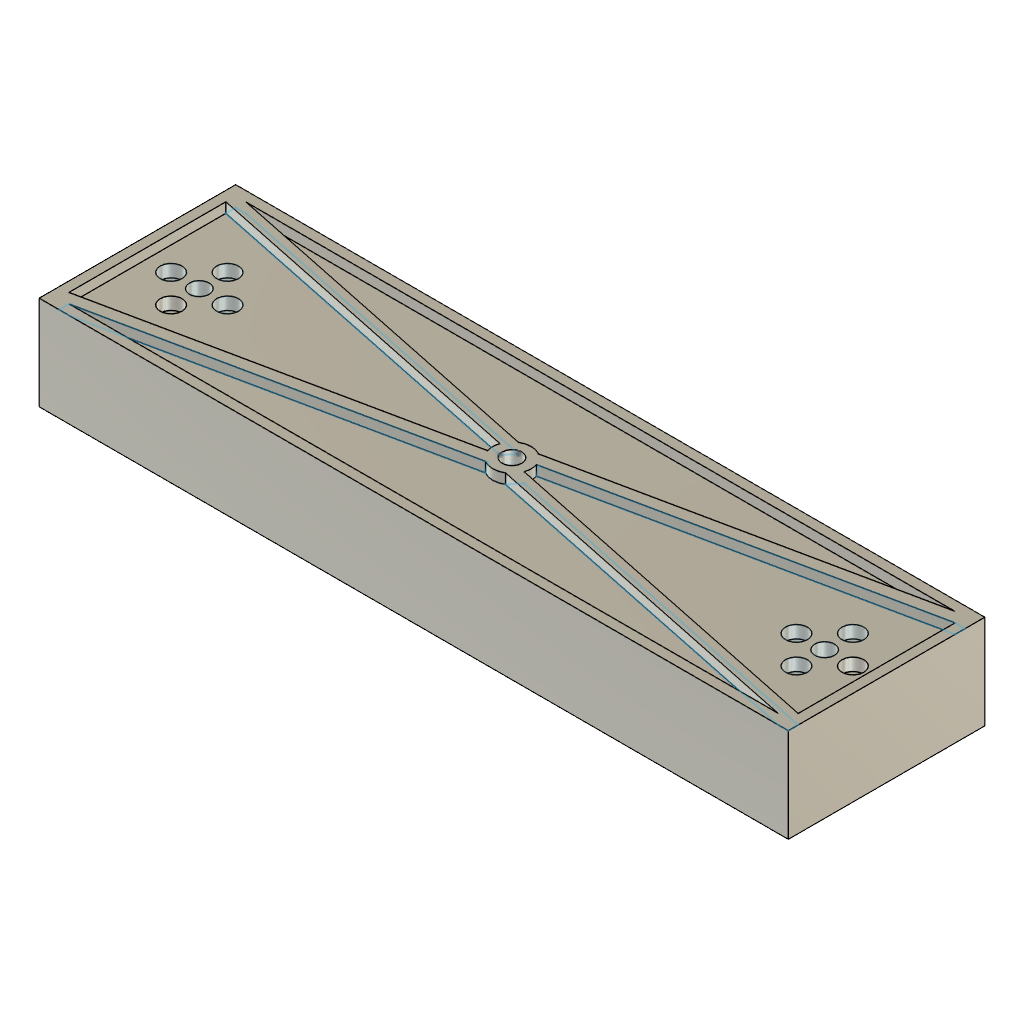
Redesigned_Cossplate (Autodesk Fusion 360 design; units mm, degrees)
part number: 2026-11-11-17-12-47-965
part number: 2026-11-11-17-17-20-266
Autodesk Fusion 360 part; units mm, degrees
sketch "Sketch1" plane through (0, 0, 0) normal (0, 0, 1) x (1, 0, 0)
  line L0 (190.5, 50) -> (-190.5, 50)
  line L1 (-190.5, 50) -> (-190.5, -50)
  line L2 (-190.5, -50) -> (190.5, -50)
  line L3 (190.5, -50) -> (190.5, 50)
  line L4 (190.5, 50) -> (-190.5, -50) construction
  line L5 (-190.5, 50) -> (190.5, -50) construction
  dimension "d1" = 381
  dimension "d2" = 100
  constraint horizontal L0
  constraint perpendicular L0 L1
  constraint parallel L0 L2
  constraint parallel L1 L3
  constraint coincident L4 origin
  constraint coincident L5 origin
  measures "d1" distance of L1.end L2.end
  measures "d2" distance of L0.end L1.end
extrude "Extrude1" add sketch "Sketch1" along normal blind 42.8 makes body 1
sketch "Sketch2" plane through (0, 0, 42.8) normal (0, 0, 1) x (-1, 0, 0)
  line L0 (-190.5, 50) -> (-190.5, -50)
  line L1 (-190.5, -50) -> (190.5, -50)
  line L2 (190.5, -50) -> (190.5, 50)
  line L3 (190.5, 50) -> (-190.5, 50)
  line L4 (190.5, 0) -> (-190.5, 0)
  line L5 (0, -50) -> (0, 50)
  circle A0 centre (159, 0) radius 14.351 construction
  circle A1 centre (159, 0) radius 5
  line L6 (159, -14.351) -> (159, 14.351) construction
  circle A2 centre (-159, 0) radius 14.351 construction
  circle A3 centre (-159, 0) radius 5
  circle A4 centre (0, 0) radius 5
  point P0 (144.649, 0)
  point P1 (173.351, 0)
  point P2 (159, -14.351)
  point P3 (159, 14.351)
  point P4 (-159, -14.351)
  point P5 (-144.649, 0)
  point P6 (-159, 14.351)
  point P7 (-173.351, 0)
  point P8 (-159, -14.351)
  point P9 (-173.351, 0)
  point P10 (-159, 14.351)
  point P11 (-144.649, 0)
  dimension "d5" = 28.702
  dimension "d6" = 10
  dimension "d7" = 31.5
  constraint midpoint L2 L4.start
  constraint midpoint L0 L4.end
  constraint midpoint L1 L5.start
  constraint midpoint L3 L5.end
  constraint coincident L4 A0.centre
  constraint concentric A0 A1
  constraint coincident A0 P0
  constraint coincident L4 P0
  constraint coincident A0 P1
  constraint coincident L4 P1
  constraint coincident A0 P2
  constraint coincident A0 P3
  constraint coincident P2 L6.start
  constraint coincident P3 L6.end
  constraint vertical L6
  constraint coincident A0.centre L6
  constraint symmetric L5 A0 A2
  constraint symmetric L5 A1 A3
  constraint symmetric L5 P0 P5
  constraint symmetric L5 P1 P9
  constraint symmetric L5 P2 P8
  constraint symmetric L5 P3 P10
  constraint coincident A4.centre origin
  constraint equal A1 A4
  constraint coincident P8 P4
  constraint coincident P9 P7
  constraint coincident P10 P6
  constraint coincident P11 P5
  measures "d5" diameter of A0
  measures "d6" diameter of A1
  measures "d7" distance of L2 A0.centre
hole "Hole1" at (-159, 14.351, 42.8) at (-144.649, 0, 42.8) at (-159, -14.351, 42.8) at (-173.351, 0, 42.8) at (144.649, 0, 42.8) at (159, 14.351, 42.8) at (173.351, 0, 42.8) at (159, -14.351, 42.8) direction (0, 0, -1) diameter 6.7564 depth 53.34 tip angle 118 counterbore diameter 11.1252 counterbore depth 6.35 bodies 1
extrude "Extrude2" cut sketch "Sketch2" against normal through all contours L4 A3 | L4 A3 | L4 L5 A4 | L4 L5 A4 | L4 L5 A4 | L4 L5 A4 | L4 A1 | L4 A1 bodies 1
copy_body "Body->Comp1" bodies 1 removing the originals makes body 2 in component "Cross Head Plate"
sketch "Sketch3" plane through (0, 0, 0) normal (0, 0, -1) x (1, 0, 0)
  circle A0 centre (173.351, 0) radius 3.3782
  circle A1 centre (144.649, 0) radius 3.3782
  circle A2 centre (-159, 14.351) radius 3.3782
  circle A3 centre (-159, -14.351) radius 3.3782
  circle A4 centre (-144.649, 0) radius 3.3782
  circle A5 centre (-173.351, 0) radius 3.3782
  circle A6 centre (159, -14.351) radius 3.3782
  circle A7 centre (159, 14.351) radius 3.3782
  line L0 (190.5, -50) -> (190.5, 50)
  line L1 (190.5, 50) -> (-190.5, 50)
  line L2 (-190.5, 50) -> (-190.5, -50)
  line L3 (-190.5, -50) -> (190.5, -50)
  circle A8 centre (159, 0) radius 5
  circle A9 centre (0, 0) radius 5
  circle A10 centre (-159, 0) radius 5
  circle A11 centre (-159, 0) radius 20.32
  circle A12 centre (159, 0) radius 20.32
  dimension "d19" = 40.64
  dimension "d20" = 40.64
  constraint concentric A10 A11
  constraint concentric A8 A12
  measures "d19" diameter of A11
  measures "d20" diameter of A12
split_face "SplitFace1" 1 faces at (0, -35, 0) by curves path "Sketch3" along A11 on bodies 2 in component "Cross Head Plate"
sketch "Sketch4" plane through (0, 0, 0) normal (0, 0, -1) x (1, 0, 0)
  circle A0 centre (-159, 0) radius 20.32
  circle A1 centre (173.351, 0) radius 3.3782
  circle A2 centre (144.649, 0) radius 3.3782
  circle A3 centre (159, -14.351) radius 3.3782
  circle A4 centre (159, 14.351) radius 3.3782
  line L0 (190.5, -50) -> (190.5, 50)
  line L1 (190.5, 50) -> (-190.5, 50)
  line L2 (-190.5, 50) -> (-190.5, -50)
  line L3 (-190.5, -50) -> (190.5, -50)
  circle A5 centre (159, 0) radius 5
  circle A6 centre (0, 0) radius 5
  circle A7 centre (159, 0) radius 20.32
  dimension "d21" = 40.64
  constraint concentric A5 A7
  measures "d21" diameter of A7
split_face "SplitFace2" 1 faces at (0, -35, 0) by curves path "Sketch4" along A7 on bodies 2 in component "Cross Head Plate"
sketch "Sketch5" plane through (0, 0, 42.8) normal (0, 0, 1) x (-1, 0, 0)
  circle A0 centre (0, 0) radius 9.7983
  constraint coincident A0.centre origin
emboss "Emboss1" depth 5.08 profiles "Sketch5" section 1 onto face at (0, -35, 42.8) on bodies 2 bodies 2 in component "Cross Head Plate"
sketch "Sketch6" plane through (0, 0, 42.8) normal (0, 0, 1) x (-1, 0, 0)
  circle A0 centre (159, 0) radius 5
  circle A1 centre (-159, 0) radius 5
  line L0 (-190.5, 50) -> (-190.5, -50)
  line L1 (-190.5, -50) -> (190.5, -50)
  line L2 (190.5, -50) -> (190.5, 50)
  line L3 (190.5, 50) -> (-190.5, 50)
  circle A2 centre (-159, 14.351) radius 5.5626
  circle A3 centre (-159, -14.351) radius 5.5626
  circle A4 centre (173.351, 0) radius 5.5626
  circle A5 centre (144.649, 0) radius 5.5626
  circle A6 centre (159, -14.351) radius 5.5626
  circle A7 centre (159, 14.351) radius 5.5626
  circle A8 centre (-144.649, 0) radius 5.5626
  circle A9 centre (-173.351, 0) radius 5.5626
  circle A10 centre (0, 0) radius 9.7983
  line L4 (185.42, 44.92) -> (-185.42, 44.92)
  line L5 (-185.42, 44.92) -> (-185.42, -44.92)
  line L6 (-185.42, -44.92) -> (185.42, -44.92)
  line L7 (185.42, -44.92) -> (185.42, 44.92)
  dimension "d28" = -5.08
extrude "Extrude2'" add sketch "Sketch6" along normal blind 5.08 contours L0 L1 L2 L3 bodies 2 in component "Cross Head Plate"
sketch "Sketch7" plane through (0, 0, 42.8) normal (0, 0, 1) x (-1, 0, 0)
  circle A0 centre (0, 0) radius 9.7983
  circle A1 centre (-144.649, 0) radius 5.5626
  circle A2 centre (159, -14.351) radius 5.5626
  circle A3 centre (144.649, 0) radius 5.5626
  circle A4 centre (173.351, 0) radius 5.5626
  circle A5 centre (-159, -14.351) radius 5.5626
  circle A6 centre (-159, 14.351) radius 5.5626
  circle A7 centre (-159, 0) radius 5
  circle A8 centre (159, 0) radius 5
  line L0 (180.1115, -44.92) -> (5.0849, -8.3755)
  line L1 (9.2876, -3.122) -> (185.42, -39.8973)
  line L2 (185.42, -39.8973) -> (185.42, -44.92)
  line L3 (5.0849, -8.3755) -> (9.2876, -3.122)
  line L4 (180.1115, 44.92) -> (5.0849, 8.3755)
  line L5 (5.0849, 8.3755) -> (9.2876, 3.122)
  line L6 (9.2876, 3.122) -> (185.42, 39.8973)
  line L7 (185.42, 39.8973) -> (185.42, 44.92)
  line L8 (-180.1115, -44.92) -> (-5.0849, -8.3755)
  line L9 (-5.0849, -8.3755) -> (-9.2876, -3.122)
  line L10 (-9.2876, -3.122) -> (-185.42, -39.8973)
  line L11 (-185.42, -39.8973) -> (-185.42, -44.92)
  line L12 (-5.0849, 8.3755) -> (-9.2876, 3.122)
  line L13 (-180.1115, 44.92) -> (-5.0849, 8.3755)
  line L14 (-9.2876, 3.122) -> (-185.42, 39.8973)
  line L15 (-185.42, 39.8973) -> (-185.42, 44.92)
  line L16 (185.42, -44.92) -> (180.1115, -44.92)
  line L17 (185.42, 44.92) -> (180.1115, 44.92)
  line L18 (-185.42, 44.92) -> (-180.1115, 44.92)
  line L19 (-180.1115, -44.92) -> (-185.42, -44.92)
  constraint coincident A0 L0.end
  constraint coincident A0 L1.start
  constraint parallel L0 L1
  constraint perpendicular L2 L16
  constraint perpendicular L7 L17
  constraint perpendicular L15 L18
  constraint perpendicular L11 L19
extrude "Extrude4" add sketch "Sketch7" along normal blind 5.08 contours A0 L4 L6 L7 L17 | A0 L0 L1 L2 L16 | A0 L13 L14 L15 L18 | A0 L8 L10 L11 L19 bodies 2 in component "Cross Head Plate"
component "Cross Head Plate" placed x (1, 0, 0) y (0, 1, 0) z (0, 0, 1) at (0, 0, 0)
equation "Crosshead_Length = 15 in"
equation "Crosshead_width = 3.937 in"
equation "Crosshead_Depth = 1.685 in"
equation "Fastener_Hole_Template = 1.13 in"
equation "Fastener_Holes = 0.438 in" comment "ANSI 1/4 Socket Head Cap Screws"
